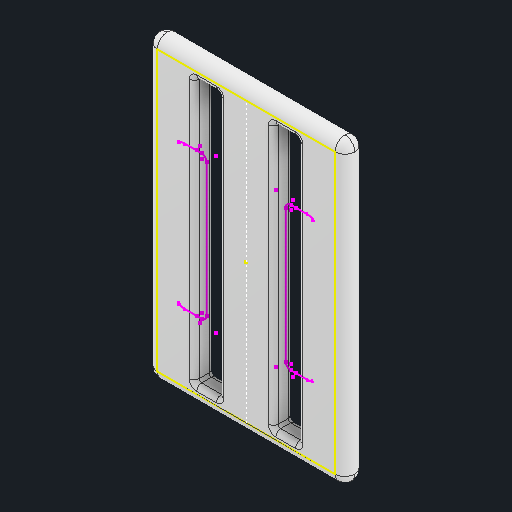
# Autodesk Inventor part: hook.01
Saved by Autodesk Inventor 2026.2 (Build 302298010, 298A)
## iProperties
Created: 2026-04-16
Part Number: hook.01
Material: POM Celcon M90 (Celanese)
Document SubType Name: Modeling
Designer: user
Density: 1.41 g/cm^3
Appearance: Smooth - White
Description: Copy of hook.02 (from hook.01) - plate 31 x 35 x 4 with R2 rim, two slots 28 x 5 mm (sketch Slots_v3), outer bars 5 mm, centre bar 11 mm, end bars 3.5 mm, slot edges R0.5. Old slot cut (Extrusion2/Fillet2) suppressed. POM Celcon M90. M1-M7 v3 C.3.6.
Mass: 10.0007 g
Surface Area: 49.4303 cm^2
Volume: 7.09271 cm^3
Author: user
Autodesk Inventor part; units mm, degrees
ref_plane "YZ Plane" through (0, 0, 0) normal (1, 0, 0) x (0, 1, 0)
ref_plane "XZ Plane" through (0, 0, 0) normal (0, 1, 0) x (-1, 0, 0)
ref_plane "XY Plane" through (0, 0, 0) normal (0, 0, 1) x (1, 0, 0)
sketch "Sketch1" plane through (0, 0, 0) normal (0, 0, 1) x (1, 0, 0)
  line L0 (20, -30.25) -> (-20, -30.25)
  line L1 (-20, -30.25) -> (-20, 30.25)
  line L2 (-20, 30.25) -> (20, 30.25)
  line L3 (20, 30.25) -> (20, -30.25)
  line L4 (20, -30.25) -> (-20, 30.25) construction
  line L5 (-20, -30.25) -> (20, 30.25) construction
  point P0 (0, 0)
  dimension "d0" = 40
  dimension "d1" = 60.5
  constraints: 12 end point, 2 midpoint, 2 parallel, 1 horizontal, 1 perpendicular
  measures "d0" distance of L1.end L2.end
  measures "d1" distance of L0.end L1.end
extrude "Extrusion1" add sketch "Sketch1" along normal blind 4
fillet "Fillet1" radius 2 12 edges at (0, 30.25, 4) (0, 30.25, 0) (-20, 30.25, 2) (-20, 0, 4) (-20, 0, 0) (-20, -30.25, 2) (0, -30.25, 4) (0, -30.25, 0) (20, -30.25, 2) (20, 0, 4) (20, 30.25, 2) (20, 0, 0)
sketch "Sketch2" plane through (0, 0, 4) normal (0, 0, 1) x (1, 0, 0)
  line L0 (-18, -28.25) -> (-18, 28.25) projected
  line L1 (18, -28.25) -> (-18, -28.25) projected
  line L2 (18, 28.25) -> (18, -28.25) projected
  line L3 (-18, 28.25) -> (18, 28.25) projected
  line L4 (-20, 28.25) -> (-18, 28.25) projected
  line L5 (-18, 28.25) -> (-18, -28.25)
  line L6 (18, -28.25) -> (18, 28.25)
  line L7 (-18, 28.25) -> (18, -28.25) construction
  line L8 (-13, 26.75) -> (-13, -26.75)
  line L9 (-18, -28.25) -> (18, -28.25) projected
  line L10 (13, -26.75) -> (13, 26.75)
  line L11 (18, -26.75) -> (-18, -26.75)
  line L12 (-18, 26.75) -> (18, 26.75)
  point P0 (0, 0)
  point P1 (18, 26.75)
  point P2 (18, -26.75)
  point P3 (-18, 26.75)
  dimension "d5" = 36
  dimension "d6" = 5
  dimension "d7" = 5
  dimension "d8" = 1.5
  dimension "d9" = 1.5
  constraints: 14 end point, 8 point on line, 4 perpendicular, 2 collinear
  measures "d5" distance of L0.end L2.start
  measures "d6" distance between parallel lines of L8 L0
  measures "d7" distance between parallel lines of L2 L10
  measures "d8" distance between parallel lines of L3 L12
  measures "d9" distance between parallel lines of L1 L11
extrude "Extrusion2" [suppressed]
fillet "Fillet2" [suppressed]
sketch "Sketch5" plane through (0, 0, 4) normal (0, 0, 1) x (1, 0, 0)
  line L0 (-18, -28.25) -> (-18, 28.25) projected
  line L1 (18, -28.25) -> (-18, -28.25) projected
  line L2 (18, 28.25) -> (18, -28.25) projected
  line L3 (9, -14.5) -> (12.4314, -14.5) projected
  arc A0 (8, -13.5) -> (9, -14.5) centre (9, -13.5) ccw projected
  line L4 (8, 13.5) -> (8, -13.5) projected
  arc A1 (9, 14.5) -> (8, 13.5) centre (9, 13.5) ccw projected
  line L5 (12.4314, 14.5) -> (9, 14.5) projected
  line L6 (18, 28.25) -> (18, -28.25) projected
  line L7 (-18, 28.25) -> (18, 28.25) projected
  line L8 (-18, -28.25) -> (-18, 28.25) projected
  line L9 (-9, 14.5) -> (-12.4314, 14.5) projected
  arc A2 (-8, 13.5) -> (-9, 14.5) centre (-9, 13.5) ccw projected
  line L10 (-8, -13.5) -> (-8, 13.5) projected
  arc A3 (-9, -14.5) -> (-8, -13.5) centre (-9, -13.5) ccw projected
  line L11 (-12.4314, -14.5) -> (-9, -14.5) projected
  line L12 (0, 28.25) -> (0, -28.25) construction
  point P0 (-13.5, -14.2529)
  point P1 (13.5, -14.2529)
  point P2 (13.5, 14.2529)
  point P3 (-13.5, 14.2529)
  point P4 (0, 0)
  point P5 (10, -14.5)
  point P6 (10, 14.5)
  point P7 (-10, 14.5)
  point P8 (-10, -14.5)
  point P9 (-9.4314, -15.5)
  point P10 (9.4314, -15.5)
  point P11 (6, -15.5)
  point P12 (6, 15.5)
  point P13 (9.4314, 15.5)
  point P14 (-9.4314, 15.5)
  point P15 (-6, 15.5)
  point P16 (-6, -15.5)
  point P17 (-13.5, -14)
  point P18 (13.5, 14)
  constraints: 2 end point, 12 other
sketch "Slots_v3" plane through (0, 0, 0) normal (0, 0, 1) x (1, 0, 0)
  line L0 (-10.5, -14) -> (-5.5, -14)
  line L1 (-5.5, -14) -> (-5.5, 39.5)
  line L2 (-5.5, 39.5) -> (-10.5, 39.5)
  line L3 (-10.5, 39.5) -> (-10.5, -14)
  line L4 (5.5, -14) -> (10.5, -14)
  line L5 (10.5, -14) -> (10.5, 14)
  line L6 (10.5, 14) -> (5.5, 14)
  line L7 (5.5, 14) -> (5.5, -14)
  dimension "d13" = 5
  dimension "d14" = 53.5
  dimension "d15" = 5
  constraints: 16 end point, 4 parallel, 2 horizontal, 2 perpendicular
  measures "d13" distance of L1.end L2.end
  measures "d14" distance of L2.end L0.start
  measures "d15" distance of L5.end L6.end
extrude "Slots_28x5" [suppressed]
fillet "Slot_edge_R0.5" [suppressed]
sketch "Slots_v4_53.5x5" plane through (0, 0, 0) normal (0, 0, 1) x (1, 0, 0)
  line L0 (5.5, -26.75) -> (10.5, -26.75)
  line L1 (10.5, -26.75) -> (10.5, 26.75)
  line L2 (10.5, 26.75) -> (5.5, 26.75)
  line L3 (5.5, 26.75) -> (5.5, -26.75)
  line L4 (-10.5, -26.75) -> (-5.5, -26.75)
  line L5 (-5.5, -26.75) -> (-5.5, 26.75)
  line L6 (-5.5, 26.75) -> (-10.5, 26.75)
  line L7 (-10.5, 26.75) -> (-10.5, -26.75)
  constraints: 16 end point, 4 parallel, 2 horizontal, 2 perpendicular
extrude "Slots_53.5x5" cut sketch "Slots_v4_53.5x5" along normal mid plane 10
fillet "Slot_corners_R0.5" radius 0.5 8 edges at (10.5, 26.75, 2) (10.5, -26.75, 2) (5.5, -26.75, 2) (5.5, 26.75, 2) (-5.5, 26.75, 2) (-5.5, -26.75, 2) (-10.5, -26.75, 2) (-10.5, 26.75, 2)
fillet "Face_edges_R1.0" radius 1 32 edges at (5.5, 0, 0) (5.6464, -26.6036, 0) (8, -26.75, 0) (10.3536, -26.6036, 0) (10.5, 0, 0) (10.3536, 26.6036, 0) (8, 26.75, 0) (5.6464, 26.6036, 0) (-10.5, 0, 0) (-10.3536, -26.6036, 0) (-8, -26.75, 0) (-5.6464, -26.6036, 0) (-5.5, 0, 0) (-5.6464, 26.6036, 0) (-8, 26.75, 0) (-10.3536, 26.6036, 0) (5.5, 0, 4) (5.6464, 26.6036, 4) (8, 26.75, 4) (10.3536, 26.6036, 4) (10.5, 0, 4) (10.3536, -26.6036, 4) (8, -26.75, 4) (5.6464, -26.6036, 4) (-10.5, 0, 4) (-10.3536, 26.6036, 4) (-8, 26.75, 4) (-5.6464, 26.6036, 4) (-5.5, 0, 4) (-5.6464, -26.6036, 4) (-8, -26.75, 4) (-10.3536, -26.6036, 4)
equation "\"d7\" = d6"
equation "\"d9\" = d8"
equation "\"d13\" = slot_width"
equation "\"d14\" = slot_length"
equation "\"d15\" = slot_width"
equation "\"slot_length\" = 53.5"
equation "\"slot_width\" = 5"
equation "\"outer_bar\" = 9.5"
body "Solid1"
